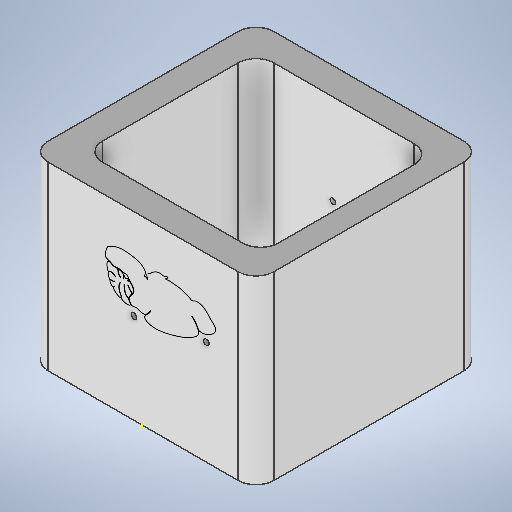
# Autodesk Inventor part: Brain Embedding Chamber 1
Saved by Autodesk Inventor 2025.2 (Build 292293000, 293)
## iProperties
Created: 2020-01-29
Part Number: Brain Embedding Chamber 1
Material: Generic
Document SubType Name: Modeling
Designer: stownsend
Density: 1 g/cm^3
Appearance: Default
Mass: 5.08661 g
Surface Area: 39.3201 cm^2
Volume: 5.08661 cm^3
Author: stownsend
Autodesk Inventor part; units mm, degrees
ref_plane "YZ Plane" through (0, 0, 0) normal (1, 0, 0) x (0, 1, 0)
ref_plane "XZ Plane" through (0, 0, 0) normal (0, 1, 0) x (-1, 0, 0)
ref_plane "XY Plane" through (0, 0, 0) normal (0, 0, 1) x (1, 0, 0)
sketch "Sketch1" plane through (0, 0, 0) normal (0, 0, 1) x (1, 0, 0)
  line L0 (12.5, -12.5) -> (-12.5, -12.5)
  line L1 (-12.5, -12.5) -> (-12.5, 12.5)
  line L2 (-12.5, 12.5) -> (12.5, 12.5)
  line L3 (12.5, 12.5) -> (12.5, -12.5)
  line L4 (9.5, -9.5) -> (-10, -9.5)
  line L5 (-10, -9.5) -> (-10, 9.5)
  line L6 (-10, 9.5) -> (9.5, 9.5)
  line L7 (9.5, 9.5) -> (9.5, -9.5)
  point P0 (0, 0)
  point P1 (-10, -12.5)
  point P2 (12.5, -9.5)
  point P3 (9.5, 12.5)
  point P4 (-12.5, 9.5)
  dimension "d51" = 25
  dimension "d52" = 25
  dimension "d53" = 12.5
  dimension "d54" = 12.5
  dimension "d55" = 19
  dimension "d56" = 9.5
  dimension "d57" = 9.5
  dimension "d58" = 10
  constraints: 16 end point, 4 parallel, 4 point on line, 2 horizontal, 2 perpendicular
  measures "d51" distance between parallel lines of L1 L3
  measures "d52" distance between parallel lines of L2 L0
  measures "d53" distance from line of L3 point (0, 0)
  measures "d54" distance from line of L0 point (0, 0)
  measures "d55" distance between parallel lines of L6 L4
  measures "d56" distance from line of L4 point (0, 0)
  measures "d57" distance from line of L7 point (0, 0)
  measures "d58" distance from line of L5 point (0, 0)
extrude "Extrusion1" add sketch "Sketch1" along normal blind 20
sketch "Sketch2" plane through (-10.5, 12.5, 0) normal (0, 1, 0) x (1, 0, 0)
  circle A0 centre (3.5, -11.5) radius 0.3
  circle A1 centre (11.5, -10) radius 0.3
  line L0 (23, 0) -> (-2, 0) projected
  point P0 (10.5, 0)
  point P1 (10.5, 0)
  dimension "d14" = 0.6
  dimension "d19" = 0.6
  dimension "d60" = 1
  dimension "d61" = 7
  dimension "d62" = 10
  dimension "d63" = 11.5
  constraints: 2 centre point, 2 midpoint
  measures "d14" diameter of A0
  measures "d19" diameter of A1
  measures "d60" horizontal distance of A1.centre point (10.5, 0)
  measures "d61" horizontal distance of A0.centre point (10.5, 0)
  measures "d62" distance from line of A1.centre L0
  measures "d63" distance from line of A0.centre L0
extrude "Extrusion2" cut sketch "Sketch2" against normal through all
fillet "Fillet1" radius 2 8 edges at (12.5, -12.5, 10) (12.5, 12.5, 10) (-12.5, 12.5, 10) (-12.5, -12.5, 10) (-10, -9.5, 10) (9.5, -9.5, 10) (9.5, 9.5, 10) (-10, 9.5, 10)
sketch "Sketch4" plane through (-10.5, 12.5, 0) normal (0, 1, 0) x (1, 0, 0)
  line L0 (17.279, -18.4469) -> (4.767, -18.4469) construction
  line L1 (4.767, -18.4469) -> (4.767, -12.4469) construction
  line L2 (4.767, -12.4469) -> (17.279, -12.4469) construction
  line L3 (17.279, -12.4469) -> (17.279, -18.4469) construction
  line L4 (21, -20) -> (0, -20) projected
  point P0 (10.5, 0)
  point P1 (23, -20)
  dimension "d106" = 6
  constraints: 1 parallel, 2 other
  measures "d106" distance between parallel lines of L2 L0
sketch "Sketch5" plane through (-10.5, 12.5, 0) normal (0, 1, 0) x (1, 0, 0)
  spline S0 degree 3 poles (5.1123, -13.1896) (5.096, -13.1961) (5.108, -13.1965) (5.0864, -13.1907) knots 0 0 0 0 0.017241 0.017241 0.017241 0.017241
  line L0 (5.1123, -13.1896) -> (5.096, -13.1961) construction
  line L1 (5.096, -13.1961) -> (5.108, -13.1965) construction
  line L2 (5.108, -13.1965) -> (5.0864, -13.1907) construction
  line L3 (5.0864, -13.1907) -> (5.0039, -13.1365)
  spline S1 degree 3 poles (5.0039, -13.1365) (5.0039, -13.1365) (4.9623, -13.1032) (4.9281, -13.0724) (4.8931, -13.041) knots 0.034483 0.034483 0.034483 0.034483 0.034483 0.051724 0.051724 0.051724 0.051724
  line L4 (5.0039, -13.1365) -> (4.9623, -13.1032) construction
  line L5 (4.9623, -13.1032) -> (4.9281, -13.0724) construction
  line L6 (4.9281, -13.0724) -> (4.8931, -13.041) construction
  spline S2 degree 3 poles (4.8931, -13.041) (4.8929, -13.0409) (4.7138, -12.8805) (4.5052, -12.5523) (4.4022, -12.325) knots 0.051724 0.051724 0.051724 0.051724 0.051724 0.068966 0.068966 0.068966 0.068966
  line L7 (4.8931, -13.041) -> (4.7138, -12.8805) construction
  line L8 (4.7138, -12.8805) -> (4.5052, -12.5523) construction
  line L9 (4.5052, -12.5523) -> (4.4022, -12.325) construction
  spline S3 degree 3 poles (4.4022, -12.325) (4.4021, -12.3249) (4.34, -12.1879) (4.341, -12.1899) (4.1753, -12.1554) knots 0.068966 0.068966 0.068966 0.068966 0.068966 0.086207 0.086207 0.086207 0.086207
  line L10 (4.4022, -12.325) -> (4.34, -12.1879) construction
  line L11 (4.34, -12.1879) -> (4.341, -12.1899) construction
  line L12 (4.341, -12.1899) -> (4.1753, -12.1554) construction
  spline S4 degree 3 poles (4.1753, -12.1554) (4.1752, -12.1554) (4.0583, -12.131) (3.9256, -12.1327) (3.8067, -12.153) knots 0.086207 0.086207 0.086207 0.086207 0.086207 0.103448 0.103448 0.103448 0.103448
  line L13 (4.1753, -12.1554) -> (4.0583, -12.131) construction
  line L14 (4.0583, -12.131) -> (3.9256, -12.1327) construction
  line L15 (3.9256, -12.1327) -> (3.8067, -12.153) construction
  spline S5 degree 3 poles (3.8067, -12.153) (3.8063, -12.1531) (3.3247, -12.2353) (2.4352, -12.7003) (2.4577, -13.2206) knots 0.103448 0.103448 0.103448 0.103448 0.103448 0.12069 0.12069 0.12069 0.12069
  line L16 (3.8067, -12.153) -> (3.3247, -12.2353) construction
  line L17 (3.3247, -12.2353) -> (2.4352, -12.7003) construction
  line L18 (2.4352, -12.7003) -> (2.4577, -13.2206) construction
  spline S6 degree 3 poles (2.4577, -13.2206) (2.4578, -13.2209) (2.4706, -13.5187) (2.875, -13.7739) (3.094, -13.9982) knots 0.12069 0.12069 0.12069 0.12069 0.12069 0.137931 0.137931 0.137931 0.137931
  line L19 (2.4577, -13.2206) -> (2.4706, -13.5187) construction
  line L20 (2.4706, -13.5187) -> (2.875, -13.7739) construction
  line L21 (2.875, -13.7739) -> (3.094, -13.9982) construction
  spline S7 degree 3 poles (3.094, -13.9982) (3.0941, -13.9984) (3.2705, -14.1792) (3.2769, -14.2582) (3.5814, -14.5112) knots 0.137931 0.137931 0.137931 0.137931 0.137931 0.155172 0.155172 0.155172 0.155172
  line L22 (3.094, -13.9982) -> (3.2705, -14.1792) construction
  line L23 (3.2705, -14.1792) -> (3.2769, -14.2582) construction
  line L24 (3.2769, -14.2582) -> (3.5814, -14.5112) construction
  spline S8 degree 3 poles (3.5814, -14.5112) (3.5815, -14.5113) (3.7107, -14.6187) (3.8864, -14.7527) (4.0976, -14.8053) knots 0.155172 0.155172 0.155172 0.155172 0.155172 0.172414 0.172414 0.172414 0.172414
  line L25 (3.5814, -14.5112) -> (3.7107, -14.6187) construction
  line L26 (3.7107, -14.6187) -> (3.8864, -14.7527) construction
  line L27 (3.8864, -14.7527) -> (4.0976, -14.8053) construction
  spline S9 degree 3 poles (4.0976, -14.8053) (4.0983, -14.8055) (4.7988, -14.9799) (4.8466, -14.6975) (5.0482, -14.6807) knots 0.172414 0.172414 0.172414 0.172414 0.172414 0.189655 0.189655 0.189655 0.189655
  line L28 (4.0976, -14.8053) -> (4.7988, -14.9799) construction
  line L29 (4.7988, -14.9799) -> (4.8466, -14.6975) construction
  line L30 (4.8466, -14.6975) -> (5.0482, -14.6807) construction
  spline S10 degree 3 poles (5.0482, -14.6807) (5.0483, -14.6807) (5.1628, -14.6712) (5.2578, -14.7642) (5.3305, -14.8098) knots 0.189655 0.189655 0.189655 0.189655 0.189655 0.206897 0.206897 0.206897 0.206897
  line L31 (5.0482, -14.6807) -> (5.1628, -14.6712) construction
  line L32 (5.1628, -14.6712) -> (5.2578, -14.7642) construction
  line L33 (5.2578, -14.7642) -> (5.3305, -14.8098) construction
  spline S11 degree 3 poles (5.3305, -14.8098) (5.3307, -14.81) (5.554, -14.9502) (5.6458, -14.9426) (5.9056, -15.0288) knots 0.206897 0.206897 0.206897 0.206897 0.206897 0.224138 0.224138 0.224138 0.224138
  line L34 (5.3305, -14.8098) -> (5.554, -14.9502) construction
  line L35 (5.554, -14.9502) -> (5.6458, -14.9426) construction
  line L36 (5.6458, -14.9426) -> (5.9056, -15.0288) construction
  spline S12 degree 3 poles (5.9056, -15.0288) (5.9058, -15.0288) (6.1303, -15.1033) (6.2641, -15.174) (6.5235, -15.2196) knots 0.224138 0.224138 0.224138 0.224138 0.224138 0.241379 0.241379 0.241379 0.241379
  line L37 (5.9056, -15.0288) -> (6.1303, -15.1033) construction
  line L38 (6.1303, -15.1033) -> (6.2641, -15.174) construction
  line L39 (6.2641, -15.174) -> (6.5235, -15.2196) construction
  spline S13 degree 3 poles (6.5235, -15.2196) (6.5237, -15.2197) (6.764, -15.262) (7.0109, -15.2751) (7.2588, -15.2958) knots 0.241379 0.241379 0.241379 0.241379 0.241379 0.258621 0.258621 0.258621 0.258621
  line L40 (6.5235, -15.2196) -> (6.764, -15.262) construction
  line L41 (6.764, -15.262) -> (7.0109, -15.2751) construction
  line L42 (7.0109, -15.2751) -> (7.2588, -15.2958) construction
  spline S14 degree 3 poles (7.2588, -15.2958) (7.259, -15.2958) (7.3796, -15.3059) (7.5139, -15.3278) (7.6346, -15.3247) knots 0.258621 0.258621 0.258621 0.258621 0.258621 0.275862 0.275862 0.275862 0.275862
  line L43 (7.2588, -15.2958) -> (7.3796, -15.3059) construction
  line L44 (7.3796, -15.3059) -> (7.5139, -15.3278) construction
  line L45 (7.5139, -15.3278) -> (7.6346, -15.3247) construction
  spline S15 degree 3 poles (7.6346, -15.3247) (7.6347, -15.3247) (7.7382, -15.322) (7.9305, -15.272) (8.0018, -15.2926) knots 0.275862 0.275862 0.275862 0.275862 0.275862 0.293103 0.293103 0.293103 0.293103
  line L46 (7.6346, -15.3247) -> (7.7382, -15.322) construction
  line L47 (7.7382, -15.322) -> (7.9305, -15.272) construction
  line L48 (7.9305, -15.272) -> (8.0018, -15.2926) construction
  spline S16 degree 3 poles (8.0018, -15.2926) (8.0018, -15.2927) (7.9765, -15.4113) (7.8287, -15.4147) (7.7313, -15.5223) knots 0.293103 0.293103 0.293103 0.293103 0.293103 0.310345 0.310345 0.310345 0.310345
  line L49 (8.0018, -15.2926) -> (7.9765, -15.4113) construction
  line L50 (7.9765, -15.4113) -> (7.8287, -15.4147) construction
  line L51 (7.8287, -15.4147) -> (7.7313, -15.5223) construction
  spline S17 degree 3 poles (7.7313, -15.5223) (7.7314, -15.5225) (7.8044, -15.6668) (7.9468, -15.5633) (8.0568, -15.5162) knots 0.310345 0.310345 0.310345 0.310345 0.310345 0.327586 0.327586 0.327586 0.327586
  line L52 (7.7313, -15.5223) -> (7.8044, -15.6668) construction
  line L53 (7.8044, -15.6668) -> (7.9468, -15.5633) construction
  line L54 (7.9468, -15.5633) -> (8.0568, -15.5162) construction
  spline S18 degree 3 poles (8.0568, -15.5162) (8.057, -15.5161) (8.2427, -15.4365) (8.2989, -15.4745) (8.4811, -15.5169) knots 0.327586 0.327586 0.327586 0.327586 0.327586 0.344828 0.344828 0.344828 0.344828
  line L55 (8.0568, -15.5162) -> (8.2427, -15.4365) construction
  line L56 (8.2427, -15.4365) -> (8.2989, -15.4745) construction
  line L57 (8.2989, -15.4745) -> (8.4811, -15.5169) construction
  spline S19 degree 3 poles (8.4811, -15.5169) (8.4815, -15.517) (8.8733, -15.6083) (9.2876, -15.3765) (9.5573, -15.1111) knots 0.344828 0.344828 0.344828 0.344828 0.344828 0.362069 0.362069 0.362069 0.362069
  line L58 (8.4811, -15.5169) -> (8.8733, -15.6083) construction
  line L59 (8.8733, -15.6083) -> (9.2876, -15.3765) construction
  line L60 (9.2876, -15.3765) -> (9.5573, -15.1111) construction
  spline S20 degree 3 poles (9.5573, -15.1111) (9.5574, -15.111) (9.6829, -14.9875) (9.6912, -14.9796) (9.8393, -14.8854) knots 0.362069 0.362069 0.362069 0.362069 0.362069 0.37931 0.37931 0.37931 0.37931
  line L61 (9.5573, -15.1111) -> (9.6829, -14.9875) construction
  line L62 (9.6829, -14.9875) -> (9.6912, -14.9796) construction
  line L63 (9.6912, -14.9796) -> (9.8393, -14.8854) construction
  spline S21 degree 3 poles (9.8393, -14.8854) (9.8397, -14.8851) (10.2004, -14.6557) (10.0808, -14.6012) (9.9764, -14.2281) knots 0.37931 0.37931 0.37931 0.37931 0.37931 0.396552 0.396552 0.396552 0.396552
  line L64 (9.8393, -14.8854) -> (10.2004, -14.6557) construction
  line L65 (10.2004, -14.6557) -> (10.0808, -14.6012) construction
  line L66 (10.0808, -14.6012) -> (9.9764, -14.2281) construction
  spline S22 degree 3 poles (9.9764, -14.2281) (9.9764, -14.2281) (9.9888, -14.2448) (10.1102, -14.3601) (10.1335, -14.3731) knots 0.396552 0.396552 0.396552 0.396552 0.396552 0.413793 0.413793 0.413793 0.413793
  line L67 (9.9764, -14.2281) -> (9.9888, -14.2448) construction
  line L68 (9.9888, -14.2448) -> (10.1102, -14.3601) construction
  line L69 (10.1102, -14.3601) -> (10.1335, -14.3731) construction
  spline S23 degree 3 poles (10.1335, -14.3731) (10.1336, -14.3732) (10.2162, -14.4193) (10.2993, -14.3703) (10.3758, -14.3525) knots 0.413793 0.413793 0.413793 0.413793 0.413793 0.431034 0.431034 0.431034 0.431034
  line L70 (10.1335, -14.3731) -> (10.2162, -14.4193) construction
  line L71 (10.2162, -14.4193) -> (10.2993, -14.3703) construction
  line L72 (10.2993, -14.3703) -> (10.3758, -14.3525) construction
  spline S24 degree 3 poles (10.3758, -14.3525) (10.3757, -14.3528) (10.2107, -14.6815) (10.1723, -14.9044) (10.4412, -15.1446) knots 0.431034 0.431034 0.431034 0.431034 0.431034 0.448276 0.448276 0.448276 0.448276
  line L73 (10.3758, -14.3525) -> (10.2107, -14.6815) construction
  line L74 (10.2107, -14.6815) -> (10.1723, -14.9044) construction
  line L75 (10.1723, -14.9044) -> (10.4412, -15.1446) construction
  spline S25 degree 3 poles (10.4412, -15.1446) (10.4415, -15.1448) (10.6677, -15.3469) (10.789, -15.4425) (11.1716, -15.542) knots 0.448276 0.448276 0.448276 0.448276 0.448276 0.465517 0.465517 0.465517 0.465517
  line L76 (10.4412, -15.1446) -> (10.6677, -15.3469) construction
  line L77 (10.6677, -15.3469) -> (10.789, -15.4425) construction
  line L78 (10.789, -15.4425) -> (11.1716, -15.542) construction
  spline S26 degree 3 poles (11.1716, -15.542) (11.1722, -15.5421) (11.7028, -15.6801) (12.6057, -15.8176) (13.1642, -15.7029) knots 0.465517 0.465517 0.465517 0.465517 0.465517 0.482759 0.482759 0.482759 0.482759
  line L79 (11.1716, -15.542) -> (11.7028, -15.6801) construction
  line L80 (11.7028, -15.6801) -> (12.6057, -15.8176) construction
  line L81 (12.6057, -15.8176) -> (13.1642, -15.7029) construction
  spline S27 degree 3 poles (13.1642, -15.7029) (13.165, -15.7028) (13.9327, -15.5451) (13.6988, -15.5071) (14.3511, -15.2223) knots 0.482759 0.482759 0.482759 0.482759 0.482759 0.5 0.5 0.5 0.5
  line L82 (13.1642, -15.7029) -> (13.9327, -15.5451) construction
  line L83 (13.9327, -15.5451) -> (13.6988, -15.5071) construction
  line L84 (13.6988, -15.5071) -> (14.3511, -15.2223) construction
  spline S28 degree 3 poles (14.3511, -15.2223) (14.3513, -15.2223) (14.5374, -15.141) (14.6261, -14.6104) (14.6707, -14.4159) knots 0.5 0.5 0.5 0.5 0.5 0.517241 0.517241 0.517241 0.517241
  line L85 (14.3511, -15.2223) -> (14.5374, -15.141) construction
  line L86 (14.5374, -15.141) -> (14.6261, -14.6104) construction
  line L87 (14.6261, -14.6104) -> (14.6707, -14.4159) construction
  spline S29 degree 3 poles (14.6707, -14.4159) (14.6708, -14.4154) (14.7707, -13.9795) (14.398, -14.0008) (14.1194, -13.8788) knots 0.517241 0.517241 0.517241 0.517241 0.517241 0.534483 0.534483 0.534483 0.534483
  line L88 (14.6707, -14.4159) -> (14.7707, -13.9795) construction
  line L89 (14.7707, -13.9795) -> (14.398, -14.0008) construction
  line L90 (14.398, -14.0008) -> (14.1194, -13.8788) construction
  spline S30 degree 3 poles (14.1194, -13.8788) (14.1193, -13.8788) (13.9934, -13.8237) (13.8863, -13.7141) (13.7397, -13.689) knots 0.534483 0.534483 0.534483 0.534483 0.534483 0.551724 0.551724 0.551724 0.551724
  line L91 (14.1194, -13.8788) -> (13.9934, -13.8237) construction
  line L92 (13.9934, -13.8237) -> (13.8863, -13.7141) construction
  line L93 (13.8863, -13.7141) -> (13.7397, -13.689) construction
  spline S31 degree 3 poles (13.7397, -13.689) (13.7395, -13.689) (13.5914, -13.6636) (13.3739, -13.7002) (13.2228, -13.71) knots 0.551724 0.551724 0.551724 0.551724 0.551724 0.568966 0.568966 0.568966 0.568966
  line L94 (13.7397, -13.689) -> (13.5914, -13.6636) construction
  line L95 (13.5914, -13.6636) -> (13.3739, -13.7002) construction
  line L96 (13.3739, -13.7002) -> (13.2228, -13.71) construction
  spline S32 degree 3 poles (13.2228, -13.71) (13.2226, -13.71) (13.0035, -13.7242) (12.9553, -13.6552) (12.7703, -13.6094) knots 0.568966 0.568966 0.568966 0.568966 0.568966 0.586207 0.586207 0.586207 0.586207
  line L97 (13.2228, -13.71) -> (13.0035, -13.7242) construction
  line L98 (13.0035, -13.7242) -> (12.9553, -13.6552) construction
  line L99 (12.9553, -13.6552) -> (12.7703, -13.6094) construction
  spline S33 degree 3 poles (12.7703, -13.6094) (12.7701, -13.6094) (12.6255, -13.5735) (12.3495, -13.5814) (12.2703, -13.5536) knots 0.586207 0.586207 0.586207 0.586207 0.586207 0.603448 0.603448 0.603448 0.603448
  line L100 (12.7703, -13.6094) -> (12.6255, -13.5735) construction
  line L101 (12.6255, -13.5735) -> (12.3495, -13.5814) construction
  line L102 (12.3495, -13.5814) -> (12.2703, -13.5536) construction
  spline S34 degree 3 poles (12.2703, -13.5536) (12.2703, -13.5536) (12.185, -13.5236) (12.097, -13.3099) (12.0289, -13.2235) knots 0.603448 0.603448 0.603448 0.603448 0.603448 0.62069 0.62069 0.62069 0.62069
  line L103 (12.2703, -13.5536) -> (12.185, -13.5236) construction
  line L104 (12.185, -13.5236) -> (12.097, -13.3099) construction
  line L105 (12.097, -13.3099) -> (12.0289, -13.2235) construction
  spline S35 degree 3 poles (12.0289, -13.2235) (12.0287, -13.2232) (11.8155, -12.9527) (11.6568, -12.8977) (11.546, -12.5954) knots 0.62069 0.62069 0.62069 0.62069 0.62069 0.637931 0.637931 0.637931 0.637931
  line L106 (12.0289, -13.2235) -> (11.8155, -12.9527) construction
  line L107 (11.8155, -12.9527) -> (11.6568, -12.8977) construction
  line L108 (11.6568, -12.8977) -> (11.546, -12.5954) construction
  spline S36 degree 3 poles (11.546, -12.5954) (11.5459, -12.5951) (11.4123, -12.2305) (11.6883, -11.9915) (11.8188, -11.8167) knots 0.637931 0.637931 0.637931 0.637931 0.637931 0.655172 0.655172 0.655172 0.655172
  line L109 (11.546, -12.5954) -> (11.4123, -12.2305) construction
  line L110 (11.4123, -12.2305) -> (11.6883, -11.9915) construction
  line L111 (11.6883, -11.9915) -> (11.8188, -11.8167) construction
  spline S37 degree 3 poles (11.8188, -11.8167) (11.8192, -11.8163) (12.1353, -11.3929) (12.0677, -11.3291) (11.9037, -11.0782) knots 0.655172 0.655172 0.655172 0.655172 0.655172 0.672414 0.672414 0.672414 0.672414
  line L112 (11.8188, -11.8167) -> (12.1353, -11.3929) construction
  line L113 (12.1353, -11.3929) -> (12.0677, -11.3291) construction
  line L114 (12.0677, -11.3291) -> (11.9037, -11.0782) construction
  spline S38 degree 3 poles (11.9037, -11.0782) (11.9036, -11.0781) (11.8008, -10.9207) (11.8272, -10.8579) (11.5586, -10.8743) knots 0.672414 0.672414 0.672414 0.672414 0.672414 0.689655 0.689655 0.689655 0.689655
  line L115 (11.9037, -11.0782) -> (11.8008, -10.9207) construction
  line L116 (11.8008, -10.9207) -> (11.8272, -10.8579) construction
  line L117 (11.8272, -10.8579) -> (11.5586, -10.8743) construction
  spline S39 degree 3 poles (11.5586, -10.8743) (11.5584, -10.8743) (11.3758, -10.8854) (11.2786, -10.9791) (11.0879, -10.8949) knots 0.689655 0.689655 0.689655 0.689655 0.689655 0.706897 0.706897 0.706897 0.706897
  line L118 (11.5586, -10.8743) -> (11.3758, -10.8854) construction
  line L119 (11.3758, -10.8854) -> (11.2786, -10.9791) construction
  line L120 (11.2786, -10.9791) -> (11.0879, -10.8949) construction
  spline S40 degree 3 poles (11.0879, -10.8949) (11.0877, -10.8948) (10.8307, -10.7813) (10.4838, -10.6345) (10.1872, -10.8202) knots 0.706897 0.706897 0.706897 0.706897 0.706897 0.724138 0.724138 0.724138 0.724138
  line L121 (11.0879, -10.8949) -> (10.8307, -10.7813) construction
  line L122 (10.8307, -10.7813) -> (10.4838, -10.6345) construction
  line L123 (10.4838, -10.6345) -> (10.1872, -10.8202) construction
  spline S41 degree 3 poles (10.1872, -10.8202) (10.1871, -10.8202) (10.0868, -10.883) (9.9811, -11.01) (9.9058, -11.0944) knots 0.724138 0.724138 0.724138 0.724138 0.724138 0.741379 0.741379 0.741379 0.741379
  line L124 (10.1872, -10.8202) -> (10.0868, -10.883) construction
  line L125 (10.0868, -10.883) -> (9.9811, -11.01) construction
  line L126 (9.9811, -11.01) -> (9.9058, -11.0944) construction
  spline S42 degree 3 poles (9.9058, -11.0944) (9.9058, -11.0944) (9.8681, -11.1367) (9.817, -11.2039) (9.7826, -11.2567) knots 0.741379 0.741379 0.741379 0.741379 0.741379 0.758621 0.758621 0.758621 0.758621
  line L127 (9.9058, -11.0944) -> (9.8681, -11.1367) construction
  line L128 (9.8681, -11.1367) -> (9.817, -11.2039) construction
  line L129 (9.817, -11.2039) -> (9.7826, -11.2567) construction
  spline S43 degree 3 poles (9.7826, -11.2567) (9.7825, -11.2568) (9.6978, -11.3865) (9.7181, -11.4133) (9.6617, -11.4006) knots 0.758621 0.758621 0.758621 0.758621 0.758621 0.775862 0.775862 0.775862 0.775862
  line L130 (9.7826, -11.2567) -> (9.6978, -11.3865) construction
  line L131 (9.6978, -11.3865) -> (9.7181, -11.4133) construction
  line L132 (9.7181, -11.4133) -> (9.6617, -11.4006) construction
  spline S44 degree 3 poles (9.6617, -11.4006) (9.6617, -11.4005) (9.661, -11.3974) (9.6611, -11.389) (9.6613, -11.3909) knots 0.775862 0.775862 0.775862 0.775862 0.775862 0.793103 0.793103 0.793103 0.793103
  line L133 (9.6617, -11.4006) -> (9.661, -11.3974) construction
  line L134 (9.661, -11.3974) -> (9.6611, -11.389) construction
  line L135 (9.6611, -11.389) -> (9.6613, -11.3909) construction
  line L136 (9.6613, -11.3909) -> (9.6695, -11.3514)
  spline S45 degree 3 poles (9.6695, -11.3514) (9.6697, -11.3511) (9.7938, -11.0595) (10.2444, -10.7485) (10.3039, -10.5561) knots 0.810345 0.810345 0.810345 0.810345 0.810345 0.827586 0.827586 0.827586 0.827586
  line L137 (9.6695, -11.3514) -> (9.7938, -11.0595) construction
  line L138 (9.7938, -11.0595) -> (10.2444, -10.7485) construction
  line L139 (10.2444, -10.7485) -> (10.3039, -10.5561) construction
  spline S46 degree 3 poles (10.3039, -10.5561) (10.304, -10.5557) (10.4184, -10.1857) (9.7108, -10.032) (9.3808, -9.9982) knots 0.827586 0.827586 0.827586 0.827586 0.827586 0.844828 0.844828 0.844828 0.844828
  line L140 (10.3039, -10.5561) -> (10.4184, -10.1857) construction
  line L141 (10.4184, -10.1857) -> (9.7108, -10.032) construction
  line L142 (9.7108, -10.032) -> (9.3808, -9.9982) construction
  spline S47 degree 3 poles (9.3808, -9.9982) (9.38, -9.9982) (8.5982, -9.9183) (7.5679, -10.1887) (6.8197, -10.4217) knots 0.844828 0.844828 0.844828 0.844828 0.844828 0.862069 0.862069 0.862069 0.862069
  line L143 (9.3808, -9.9982) -> (8.5982, -9.9183) construction
  line L144 (8.5982, -9.9183) -> (7.5679, -10.1887) construction
  line L145 (7.5679, -10.1887) -> (6.8197, -10.4217) construction
  spline S48 degree 3 poles (6.8197, -10.4217) (6.8189, -10.422) (6.0015, -10.6767) (5.3359, -10.9294) (4.7573, -11.3751) knots 0.862069 0.862069 0.862069 0.862069 0.862069 0.87931 0.87931 0.87931 0.87931
  line L146 (6.8197, -10.4217) -> (6.0015, -10.6767) construction
  line L147 (6.0015, -10.6767) -> (5.3359, -10.9294) construction
  line L148 (5.3359, -10.9294) -> (4.7573, -11.3751) construction
  spline S49 degree 3 poles (4.7573, -11.3751) (4.757, -11.3754) (4.4623, -11.6023) (4.208, -11.8493) (4.468, -12.3551) knots 0.87931 0.87931 0.87931 0.87931 0.87931 0.896552 0.896552 0.896552 0.896552
  line L149 (4.7573, -11.3751) -> (4.4623, -11.6023) construction
  line L150 (4.4623, -11.6023) -> (4.208, -11.8493) construction
  line L151 (4.208, -11.8493) -> (4.468, -12.3551) construction
  spline S50 degree 3 poles (4.468, -12.3551) (4.4681, -12.3553) (4.545, -12.5048) (4.7304, -12.8152) (4.8396, -12.9197) knots 0.896552 0.896552 0.896552 0.896552 0.896552 0.913793 0.913793 0.913793 0.913793
  line L152 (4.468, -12.3551) -> (4.545, -12.5048) construction
  line L153 (4.545, -12.5048) -> (4.7304, -12.8152) construction
  line L154 (4.7304, -12.8152) -> (4.8396, -12.9197) construction
  spline S51 degree 3 poles (4.8396, -12.9197) (4.8397, -12.9197) (4.8777, -12.9561) (4.9002, -12.9777) (4.9368, -13.0134) knots 0.913793 0.913793 0.913793 0.913793 0.913793 0.931034 0.931034 0.931034 0.931034
  line L155 (4.8396, -12.9197) -> (4.8777, -12.9561) construction
  line L156 (4.8777, -12.9561) -> (4.9002, -12.9777) construction
  line L157 (4.9002, -12.9777) -> (4.9368, -13.0134) construction
  spline S52 degree 3 poles (4.9368, -13.0134) (4.9368, -13.0134) (4.9804, -13.0559) (4.994, -13.0696) (5.0383, -13.1024) knots 0.931034 0.931034 0.931034 0.931034 0.931034 0.948276 0.948276 0.948276 0.948276
  line L158 (4.9368, -13.0134) -> (4.9804, -13.0559) construction
  line L159 (4.9804, -13.0559) -> (4.994, -13.0696) construction
  line L160 (4.994, -13.0696) -> (5.0383, -13.1024) construction
  spline S53 degree 3 poles (5.0383, -13.1024) (5.0383, -13.1024) (5.0577, -13.1168) (5.0836, -13.1338) (5.0938, -13.1435) knots 0.948276 0.948276 0.948276 0.948276 0.948276 0.965517 0.965517 0.965517 0.965517
  line L161 (5.0383, -13.1024) -> (5.0577, -13.1168) construction
  line L162 (5.0577, -13.1168) -> (5.0836, -13.1338) construction
  line L163 (5.0836, -13.1338) -> (5.0938, -13.1435) construction
  spline S54 degree 3 poles (5.0938, -13.1435) (5.0938, -13.1435) (5.1353, -13.183) (5.1337, -13.1354) (5.1123, -13.1896) knots 0.965517 0.965517 0.965517 0.965517 0.965517 1 1 1 1
  line L164 (5.0938, -13.1435) -> (5.1353, -13.183) construction
  line L165 (5.1353, -13.183) -> (5.1337, -13.1354) construction
  line L166 (5.1337, -13.1354) -> (5.1123, -13.1896) construction
  spline S55 degree 3 poles (11.8568, -10.8808) (11.8964, -11.0254) (12.0126, -11.1302) (12.0706, -11.2605) knots 0 0 0 0 0.019231 0.019231 0.019231 0.019231
  line L167 (11.8568, -10.8808) -> (11.8964, -11.0254) construction
  line L168 (11.8964, -11.0254) -> (12.0126, -11.1302) construction
  line L169 (12.0126, -11.1302) -> (12.0706, -11.2605) construction
  spline S56 degree 3 poles (12.0706, -11.2605) (12.0706, -11.2607) (12.1282, -11.3902) (12.0622, -11.3171) (12.2122, -11.4209) knots 0.019231 0.019231 0.019231 0.019231 0.019231 0.038462 0.038462 0.038462 0.038462
  line L170 (12.0706, -11.2605) -> (12.1282, -11.3902) construction
  line L171 (12.1282, -11.3902) -> (12.0622, -11.3171) construction
  line L172 (12.0622, -11.3171) -> (12.2122, -11.4209) construction
  spline S57 degree 3 poles (12.2122, -11.4209) (12.2122, -11.4209) (12.2738, -11.4636) (12.3339, -11.5101) (12.3769, -11.558) knots 0.038462 0.038462 0.038462 0.038462 0.038462 0.057692 0.057692 0.057692 0.057692
  line L173 (12.2122, -11.4209) -> (12.2738, -11.4636) construction
  line L174 (12.2738, -11.4636) -> (12.3339, -11.5101) construction
  line L175 (12.3339, -11.5101) -> (12.3769, -11.558) construction
  spline S58 degree 3 poles (12.3769, -11.558) (12.377, -11.5582) (12.4891, -11.6831) (12.5098, -11.7844) (12.5463, -11.9908) knots 0.057692 0.057692 0.057692 0.057692 0.057692 0.076923 0.076923 0.076923 0.076923
  line L176 (12.3769, -11.558) -> (12.4891, -11.6831) construction
  line L177 (12.4891, -11.6831) -> (12.5098, -11.7844) construction
  line L178 (12.5098, -11.7844) -> (12.5463, -11.9908) construction
  spline S59 degree 3 poles (12.5463, -11.9908) (12.5464, -11.9909) (12.5641, -12.091) (12.6299, -12.4372) (12.5875, -12.5135) knots 0.076923 0.076923 0.076923 0.076923 0.076923 0.096154 0.096154 0.096154 0.096154
  line L179 (12.5463, -11.9908) -> (12.5641, -12.091) construction
  line L180 (12.5641, -12.091) -> (12.6299, -12.4372) construction
  line L181 (12.6299, -12.4372) -> (12.5875, -12.5135) construction
  spline S60 degree 3 poles (12.5875, -12.5135) (12.5875, -12.5135) (12.5205, -12.4416) (12.5789, -11.8028) (12.3409, -11.5621) knots 0.096154 0.096154 0.096154 0.096154 0.096154 0.115385 0.115385 0.115385 0.115385
  line L182 (12.5875, -12.5135) -> (12.5205, -12.4416) construction
  line L183 (12.5205, -12.4416) -> (12.5789, -11.8028) construction
  line L184 (12.5789, -11.8028) -> (12.3409, -11.5621) construction
  spline S61 degree 3 poles (12.3409, -11.5621) (12.3408, -11.5621) (12.2982, -11.519) (12.1663, -11.417) (12.0895, -11.3881) knots 0.115385 0.115385 0.115385 0.115385 0.115385 0.134615 0.134615 0.134615 0.134615
  line L185 (12.3409, -11.5621) -> (12.2982, -11.519) construction
  line L186 (12.2982, -11.519) -> (12.1663, -11.417) construction
  line L187 (12.1663, -11.417) -> (12.0895, -11.3881) construction
  spline S62 degree 3 poles (12.0895, -11.3881) (12.0895, -11.3883) (12.064, -11.5379) (11.9366, -11.7414) (11.8461, -11.86) knots 0.134615 0.134615 0.134615 0.134615 0.134615 0.153846 0.153846 0.153846 0.153846
  line L188 (12.0895, -11.3881) -> (12.064, -11.5379) construction
  line L189 (12.064, -11.5379) -> (11.9366, -11.7414) construction
  line L190 (11.9366, -11.7414) -> (11.8461, -11.86) construction
  spline S63 degree 3 poles (11.8461, -11.86) (11.8461, -11.8601) (11.8038, -11.9154) (11.7761, -11.9381) (11.7371, -11.9981) knots 0.153846 0.153846 0.153846 0.153846 0.153846 0.173077 0.173077 0.173077 0.173077
  line L191 (11.8461, -11.86) -> (11.8038, -11.9154) construction
  line L192 (11.8038, -11.9154) -> (11.7761, -11.9381) construction
  line L193 (11.7761, -11.9381) -> (11.7371, -11.9981) construction
  spline S64 degree 3 poles (11.7371, -11.9981) (11.7371, -11.9982) (11.7549, -12.076) (11.7925, -12.1251) (11.8345, -12.1637) knots 0.173077 0.173077 0.173077 0.173077 0.173077 0.192308 0.192308 0.192308 0.192308
  line L194 (11.7371, -11.9981) -> (11.7549, -12.076) construction
  line L195 (11.7549, -12.076) -> (11.7925, -12.1251) construction
  line L196 (11.7925, -12.1251) -> (11.8345, -12.1637) construction
  spline S65 degree 3 poles (11.8345, -12.1637) (11.8348, -12.164) (12.155, -12.4581) (11.9815, -12.3549) (12.1222, -12.5428) knots 0.192308 0.192308 0.192308 0.192308 0.192308 0.211538 0.211538 0.211538 0.211538
  line L197 (11.8345, -12.1637) -> (12.155, -12.4581) construction
  line L198 (12.155, -12.4581) -> (11.9815, -12.3549) construction
  line L199 (11.9815, -12.3549) -> (12.1222, -12.5428) construction
  spline S66 degree 3 poles (12.1222, -12.5428) (12.1223, -12.5428) (12.1664, -12.6017) (12.1654, -12.5633) (12.1806, -12.6356) knots 0.211538 0.211538 0.211538 0.211538 0.211538 0.230769 0.230769 0.230769 0.230769
  line L200 (12.1222, -12.5428) -> (12.1664, -12.6017) construction
  line L201 (12.1664, -12.6017) -> (12.1654, -12.5633) construction
  line L202 (12.1654, -12.5633) -> (12.1806, -12.6356) construction
  spline S67 degree 3 poles (12.1806, -12.6356) (12.1805, -12.6356) (12.064, -12.5872) (12.0564, -12.4323) (11.962, -12.3224) knots 0.230769 0.230769 0.230769 0.230769 0.230769 0.25 0.25 0.25 0.25
  line L203 (12.1806, -12.6356) -> (12.064, -12.5872) construction
  line L204 (12.064, -12.5872) -> (12.0564, -12.4323) construction
  line L205 (12.0564, -12.4323) -> (11.962, -12.3224) construction
  spline S68 degree 3 poles (11.962, -12.3224) (11.9619, -12.3223) (11.8713, -12.2168) (11.7744, -12.1896) (11.7113, -12.0314) knots 0.25 0.25 0.25 0.25 0.25 0.269231 0.269231 0.269231 0.269231
  line L206 (11.962, -12.3224) -> (11.8713, -12.2168) construction
  line L207 (11.8713, -12.2168) -> (11.7744, -12.1896) construction
  line L208 (11.7744, -12.1896) -> (11.7113, -12.0314) construction
  spline S69 degree 3 poles (11.7113, -12.0314) (11.7111, -12.0316) (11.5267, -12.2286) (11.5158, -12.4653) (11.6594, -12.7194) knots 0.269231 0.269231 0.269231 0.269231 0.269231 0.288462 0.288462 0.288462 0.288462
  line L209 (11.7113, -12.0314) -> (11.5267, -12.2286) construction
  line L210 (11.5267, -12.2286) -> (11.5158, -12.4653) construction
  line L211 (11.5158, -12.4653) -> (11.6594, -12.7194) construction
  spline S70 degree 3 poles (11.6594, -12.7194) (11.6595, -12.7195) (11.7316, -12.847) (11.7823, -12.8898) (11.874, -12.9817) knots 0.288462 0.288462 0.288462 0.288462 0.288462 0.307692 0.307692 0.307692 0.307692
  line L212 (11.6594, -12.7194) -> (11.7316, -12.847) construction
  line L213 (11.7316, -12.847) -> (11.7823, -12.8898) construction
  line L214 (11.7823, -12.8898) -> (11.874, -12.9817) construction
  spline S71 degree 3 poles (11.874, -12.9817) (11.8742, -12.9819) (12.0285, -13.1366) (12.1012, -13.0012) (12.2221, -13.0092) knots 0.307692 0.307692 0.307692 0.307692 0.307692 0.326923 0.326923 0.326923 0.326923
  line L215 (11.874, -12.9817) -> (12.0285, -13.1366) construction
  line L216 (12.0285, -13.1366) -> (12.1012, -13.0012) construction
  line L217 (12.1012, -13.0012) -> (12.2221, -13.0092) construction
  line L218 (12.2221, -13.0092) -> (12.2444, -13.0141)
  spline S72 degree 3 poles (12.2444, -13.0141) (12.2444, -13.0141) (12.1929, -13.0553) (12.0727, -13.0815) (12.0044, -13.0853) knots 0.346154 0.346154 0.346154 0.346154 0.346154 0.365385 0.365385 0.365385 0.365385
  line L219 (12.2444, -13.0141) -> (12.1929, -13.0553) construction
  line L220 (12.1929, -13.0553) -> (12.0727, -13.0815) construction
  line L221 (12.0727, -13.0815) -> (12.0044, -13.0853) construction
  spline S73 degree 3 poles (12.0044, -13.0853) (12.0047, -13.0855) (12.2672, -13.3216) (12.374, -13.1835) (12.4605, -13.1412) knots 0.365385 0.365385 0.365385 0.365385 0.365385 0.384615 0.384615 0.384615 0.384615
  line L222 (12.0044, -13.0853) -> (12.2672, -13.3216) construction
  line L223 (12.2672, -13.3216) -> (12.374, -13.1835) construction
  line L224 (12.374, -13.1835) -> (12.4605, -13.1412) construction
  spline S74 degree 3 poles (12.4605, -13.1412) (12.4606, -13.1413) (12.5373, -13.2421) (12.5434, -13.2979) (12.634, -13.3767) knots 0.384615 0.384615 0.384615 0.384615 0.384615 0.403846 0.403846 0.403846 0.403846
  line L225 (12.4605, -13.1412) -> (12.5373, -13.2421) construction
  line L226 (12.5373, -13.2421) -> (12.5434, -13.2979) construction
  line L227 (12.5434, -13.2979) -> (12.634, -13.3767) construction
  spline S75 degree 3 poles (12.634, -13.3767) (12.634, -13.3766) (12.6358, -13.2673) (12.6165, -13.1243) (12.6669, -13.0322) knots 0.403846 0.403846 0.403846 0.403846 0.403846 0.423077 0.423077 0.423077 0.423077
  line L228 (12.634, -13.3767) -> (12.6358, -13.2673) construction
  line L229 (12.6358, -13.2673) -> (12.6165, -13.1243) construction
  line L230 (12.6165, -13.1243) -> (12.6669, -13.0322) construction
  spline S76 degree 3 poles (12.6669, -13.0322) (12.6669, -13.0322) (12.6899, -13.0604) (12.6837, -13.0575) (12.6722, -13.1423) knots 0.423077 0.423077 0.423077 0.423077 0.423077 0.442308 0.442308 0.442308 0.442308
  line L231 (12.6669, -13.0322) -> (12.6899, -13.0604) construction
  line L232 (12.6899, -13.0604) -> (12.6837, -13.0575) construction
  line L233 (12.6837, -13.0575) -> (12.6722, -13.1423) construction
  spline S77 degree 3 poles (12.6722, -13.1423) (12.6722, -13.1425) (12.6437, -13.3516) (12.6592, -13.424) (12.7794, -13.5051) knots 0.442308 0.442308 0.442308 0.442308 0.442308 0.461538 0.461538 0.461538 0.461538
  line L234 (12.6722, -13.1423) -> (12.6437, -13.3516) construction
  line L235 (12.6437, -13.3516) -> (12.6592, -13.424) construction
  line L236 (12.6592, -13.424) -> (12.7794, -13.5051) construction
  spline S78 degree 3 poles (12.7794, -13.5051) (12.7795, -13.5052) (12.9325, -13.6085) (13.4542, -13.7902) (13.1692, -13.1948) knots 0.461538 0.461538 0.461538 0.461538 0.461538 0.480769 0.480769 0.480769 0.480769
  line L237 (12.7794, -13.5051) -> (12.9325, -13.6085) construction
  line L238 (12.9325, -13.6085) -> (13.4542, -13.7902) construction
  line L239 (13.4542, -13.7902) -> (13.1692, -13.1948) construction
  spline S79 degree 3 poles (13.1692, -13.1948) (13.1691, -13.1946) (13.0796, -13.0077) (12.9858, -13.0367) (12.9764, -12.9583) knots 0.480769 0.480769 0.480769 0.480769 0.480769 0.5 0.5 0.5 0.5
  line L240 (13.1692, -13.1948) -> (13.0796, -13.0077) construction
  line L241 (13.0796, -13.0077) -> (12.9858, -13.0367) construction
  line L242 (12.9858, -13.0367) -> (12.9764, -12.9583) construction
  spline S80 degree 3 poles (12.9764, -12.9583) (12.9765, -12.9583) (13.0397, -12.967) (13.1601, -13.1003) (13.194, -13.169) knots 0.5 0.5 0.5 0.5 0.5 0.519231 0.519231 0.519231 0.519231
  line L243 (12.9764, -12.9583) -> (13.0397, -12.967) construction
  line L244 (13.0397, -12.967) -> (13.1601, -13.1003) construction
  line L245 (13.1601, -13.1003) -> (13.194, -13.169) construction
  spline S81 degree 3 poles (13.194, -13.169) (13.1941, -13.1691) (13.2552, -13.2929) (13.2687, -13.3701) (13.2886, -13.5211) knots 0.519231 0.519231 0.519231 0.519231 0.519231 0.538462 0.538462 0.538462 0.538462
  line L246 (13.194, -13.169) -> (13.2552, -13.2929) construction
  line L247 (13.2552, -13.2929) -> (13.2687, -13.3701) construction
  line L248 (13.2687, -13.3701) -> (13.2886, -13.5211) construction
  spline S82 degree 3 poles (13.2886, -13.5211) (13.2886, -13.5213) (13.3215, -13.7713) (13.5924, -13.5031) (13.9718, -13.741) knots 0.538462 0.538462 0.538462 0.538462 0.538462 0.557692 0.557692 0.557692 0.557692
  line L249 (13.2886, -13.5211) -> (13.3215, -13.7713) construction
  line L250 (13.3215, -13.7713) -> (13.5924, -13.5031) construction
  line L251 (13.5924, -13.5031) -> (13.9718, -13.741) construction
  spline S83 degree 3 poles (13.9718, -13.741) (13.9719, -13.741) (14.034, -13.7799) (14.1847, -13.8799) (14.2734, -13.8584) knots 0.557692 0.557692 0.557692 0.557692 0.557692 0.576923 0.576923 0.576923 0.576923
  line L252 (13.9718, -13.741) -> (14.034, -13.7799) construction
  line L253 (14.034, -13.7799) -> (14.1847, -13.8799) construction
  line L254 (14.1847, -13.8799) -> (14.2734, -13.8584) construction
  spline S84 degree 3 poles (14.2734, -13.8584) (14.2738, -13.8583) (14.6538, -13.7665) (14.4561, -12.9774) (14.3496, -12.8614) knots 0.576923 0.576923 0.576923 0.576923 0.576923 0.596154 0.596154 0.596154 0.596154
  line L255 (14.2734, -13.8584) -> (14.6538, -13.7665) construction
  line L256 (14.6538, -13.7665) -> (14.4561, -12.9774) construction
  line L257 (14.4561, -12.9774) -> (14.3496, -12.8614) construction
  spline S85 degree 3 poles (14.3496, -12.8614) (14.3495, -12.8615) (14.2195, -12.9549) (14.1358, -13.0169) (13.9141, -12.9571) knots 0.596154 0.596154 0.596154 0.596154 0.596154 0.615385 0.615385 0.615385 0.615385
  line L258 (14.3496, -12.8614) -> (14.2195, -12.9549) construction
  line L259 (14.2195, -12.9549) -> (14.1358, -13.0169) construction
  line L260 (14.1358, -13.0169) -> (13.9141, -12.9571) construction
  spline S86 degree 3 poles (13.9141, -12.9571) (13.914, -12.9571) (13.7696, -12.9181) (13.5819, -12.8313) (13.5339, -12.7227) knots 0.615385 0.615385 0.615385 0.615385 0.615385 0.634615 0.634615 0.634615 0.634615
  line L261 (13.9141, -12.9571) -> (13.7696, -12.9181) construction
  line L262 (13.7696, -12.9181) -> (13.5819, -12.8313) construction
  line L263 (13.5819, -12.8313) -> (13.5339, -12.7227) construction
  spline S87 degree 3 poles (13.5339, -12.7227) (13.534, -12.7227) (13.5821, -12.7417) (13.9534, -13.0738) (14.2368, -12.9012) knots 0.634615 0.634615 0.634615 0.634615 0.634615 0.653846 0.653846 0.653846 0.653846
  line L264 (13.5339, -12.7227) -> (13.5821, -12.7417) construction
  line L265 (13.5821, -12.7417) -> (13.9534, -13.0738) construction
  line L266 (13.9534, -13.0738) -> (14.2368, -12.9012) construction
  spline S88 degree 3 poles (14.2368, -12.9012) (14.2369, -12.9011) (14.3616, -12.8252) (14.3808, -12.7458) (14.3449, -12.5248) knots 0.653846 0.653846 0.653846 0.653846 0.653846 0.673077 0.673077 0.673077 0.673077
  line L267 (14.2368, -12.9012) -> (14.3616, -12.8252) construction
  line L268 (14.3616, -12.8252) -> (14.3808, -12.7458) construction
  line L269 (14.3808, -12.7458) -> (14.3449, -12.5248) construction
  spline S89 degree 3 poles (14.3449, -12.5248) (14.3449, -12.5247) (14.3152, -12.3421) (14.2367, -12.3005) (14.1944, -12.1832) knots 0.673077 0.673077 0.673077 0.673077 0.673077 0.692308 0.692308 0.692308 0.692308
  line L270 (14.3449, -12.5248) -> (14.3152, -12.3421) construction
  line L271 (14.3152, -12.3421) -> (14.2367, -12.3005) construction
  line L272 (14.2367, -12.3005) -> (14.1944, -12.1832) construction
  spline S90 degree 3 poles (14.1944, -12.1832) (14.1942, -12.1833) (14.0574, -12.2028) (14.0293, -12.2118) (13.8811, -12.1968) knots 0.692308 0.692308 0.692308 0.692308 0.692308 0.711538 0.711538 0.711538 0.711538
  line L273 (14.1944, -12.1832) -> (14.0574, -12.2028) construction
  line L274 (14.0574, -12.2028) -> (14.0293, -12.2118) construction
  line L275 (14.0293, -12.2118) -> (13.8811, -12.1968) construction
  spline S91 degree 3 poles (13.8811, -12.1968) (13.8809, -12.1968) (13.693, -12.1777) (13.7312, -12.2492) (13.6295, -12.2854) knots 0.711538 0.711538 0.711538 0.711538 0.711538 0.730769 0.730769 0.730769 0.730769
  line L276 (13.8811, -12.1968) -> (13.693, -12.1777) construction
  line L277 (13.693, -12.1777) -> (13.7312, -12.2492) construction
  line L278 (13.7312, -12.2492) -> (13.6295, -12.2854) construction
  spline S92 degree 3 poles (13.6295, -12.2854) (13.6296, -12.2852) (13.6991, -12.0721) (13.9733, -12.2184) (14.1667, -12.1485) knots 0.730769 0.730769 0.730769 0.730769 0.730769 0.75 0.75 0.75 0.75
  line L279 (13.6295, -12.2854) -> (13.6991, -12.0721) construction
  line L280 (13.6991, -12.0721) -> (13.9733, -12.2184) construction
  line L281 (13.9733, -12.2184) -> (14.1667, -12.1485) construction
  spline S93 degree 3 poles (14.1667, -12.1485) (14.1667, -12.1482) (14.1947, -11.8965) (13.9774, -11.6783) (13.8099, -11.6127) knots 0.75 0.75 0.75 0.75 0.75 0.769231 0.769231 0.769231 0.769231
  line L282 (14.1667, -12.1485) -> (14.1947, -11.8965) construction
  line L283 (14.1947, -11.8965) -> (13.9774, -11.6783) construction
  line L284 (13.9774, -11.6783) -> (13.8099, -11.6127) construction
  spline S94 degree 3 poles (13.8099, -11.6127) (13.8098, -11.6128) (13.7229, -11.69) (13.7182, -11.7549) (13.6488, -11.7797) knots 0.769231 0.769231 0.769231 0.769231 0.769231 0.788462 0.788462 0.788462 0.788462
  line L285 (13.8099, -11.6127) -> (13.7229, -11.69) construction
  line L286 (13.7229, -11.69) -> (13.7182, -11.7549) construction
  line L287 (13.7182, -11.7549) -> (13.6488, -11.7797) construction
  spline S95 degree 3 poles (13.6488, -11.7797) (13.6489, -11.7796) (13.6793, -11.6882) (13.7394, -11.6567) (13.7793, -11.5853) knots 0.788462 0.788462 0.788462 0.788462 0.788462 0.807692 0.807692 0.807692 0.807692
  line L288 (13.6488, -11.7797) -> (13.6793, -11.6882) construction
  line L289 (13.6793, -11.6882) -> (13.7394, -11.6567) construction
  line L290 (13.7394, -11.6567) -> (13.7793, -11.5853) construction
  spline S96 degree 3 poles (13.7793, -11.5853) (13.7792, -11.585) (13.674, -11.24) (13.1457, -10.9584) (12.9635, -11.0099) knots 0.807692 0.807692 0.807692 0.807692 0.807692 0.826923 0.826923 0.826923 0.826923
  line L291 (13.7793, -11.5853) -> (13.674, -11.24) construction
  line L292 (13.674, -11.24) -> (13.1457, -10.9584) construction
  line L293 (13.1457, -10.9584) -> (12.9635, -11.0099) construction
  spline S97 degree 3 poles (12.9635, -11.0099) (12.9634, -11.0101) (12.8953, -11.1476) (12.9311, -11.2661) (13.0048, -11.3743) knots 0.826923 0.826923 0.826923 0.826923 0.826923 0.846154 0.846154 0.846154 0.846154
  line L294 (12.9635, -11.0099) -> (12.8953, -11.1476) construction
  line L295 (12.8953, -11.1476) -> (12.9311, -11.2661) construction
  line L296 (12.9311, -11.2661) -> (13.0048, -11.3743) construction
  spline S98 degree 3 poles (13.0048, -11.3743) (13.0049, -11.3745) (13.076, -11.4788) (13.1142, -11.5459) (13.1461, -11.6945) knots 0.846154 0.846154 0.846154 0.846154 0.846154 0.865385 0.865385 0.865385 0.865385
  line L297 (13.0048, -11.3743) -> (13.076, -11.4788) construction
  line L298 (13.076, -11.4788) -> (13.1142, -11.5459) construction
  line L299 (13.1142, -11.5459) -> (13.1461, -11.6945) construction
  spline S99 degree 3 poles (13.1461, -11.6945) (13.1462, -11.6947) (13.175, -11.8289) (13.1876, -11.9773) (13.1657, -12.1179) knots 0.865385 0.865385 0.865385 0.865385 0.865385 0.884615 0.884615 0.884615 0.884615
  line L300 (13.1461, -11.6945) -> (13.175, -11.8289) construction
  line L301 (13.175, -11.8289) -> (13.1876, -11.9773) construction
  line L302 (13.1876, -11.9773) -> (13.1657, -12.1179) construction
  spline S100 degree 3 poles (13.1657, -12.1179) (13.1656, -12.118) (13.1507, -12.2135) (13.1258, -12.285) (13.0827, -12.3655) knots 0.884615 0.884615 0.884615 0.884615 0.884615 0.903846 0.903846 0.903846 0.903846
  line L303 (13.1657, -12.1179) -> (13.1507, -12.2135) construction
  line L304 (13.1507, -12.2135) -> (13.1258, -12.285) construction
  line L305 (13.1258, -12.285) -> (13.0827, -12.3655) construction
  spline S101 degree 3 poles (13.0827, -12.3655) (13.0827, -12.3655) (13.0532, -12.4204) (13.0631, -12.4151) (13.0122, -12.4323) knots 0.903846 0.903846 0.903846 0.903846 0.903846 0.923077 0.923077 0.923077 0.923077
  line L306 (13.0827, -12.3655) -> (13.0532, -12.4204) construction
  line L307 (13.0532, -12.4204) -> (13.0631, -12.4151) construction
  line L308 (13.0631, -12.4151) -> (13.0122, -12.4323) construction
  spline S102 degree 3 poles (13.0122, -12.4323) (13.0123, -12.4321) (13.1009, -12.2007) (13.2097, -12.1102) (13.1084, -11.6682) knots 0.923077 0.923077 0.923077 0.923077 0.923077 0.942308 0.942308 0.942308 0.942308
  line L309 (13.0122, -12.4323) -> (13.1009, -12.2007) construction
  line L310 (13.1009, -12.2007) -> (13.2097, -12.1102) construction
  line L311 (13.2097, -12.1102) -> (13.1084, -11.6682) construction
  spline S103 degree 3 poles (13.1084, -11.6682) (13.1083, -11.6679) (13.036, -11.3523) (12.8277, -11.3738) (12.9345, -10.9805) knots 0.942308 0.942308 0.942308 0.942308 0.942308 0.961538 0.961538 0.961538 0.961538
  line L312 (13.1084, -11.6682) -> (13.036, -11.3523) construction
  line L313 (13.036, -11.3523) -> (12.8277, -11.3738) construction
  line L314 (12.8277, -11.3738) -> (12.9345, -10.9805) construction
  spline S104 degree 3 poles (12.9345, -10.9805) (12.9342, -10.9803) (12.6411, -10.7902) (12.1776, -10.6159) (11.8568, -10.8808) knots 0.961538 0.961538 0.961538 0.961538 0.961538 1 1 1 1
  line L315 (12.9345, -10.9805) -> (12.6411, -10.7902) construction
  line L316 (12.6411, -10.7902) -> (12.1776, -10.6159) construction
  line L317 (12.1776, -10.6159) -> (11.8568, -10.8808) construction
  point P0 (10.5, 0)
  constraints: 103 coincident, 6 end point, 534 other
body "Solid1"
